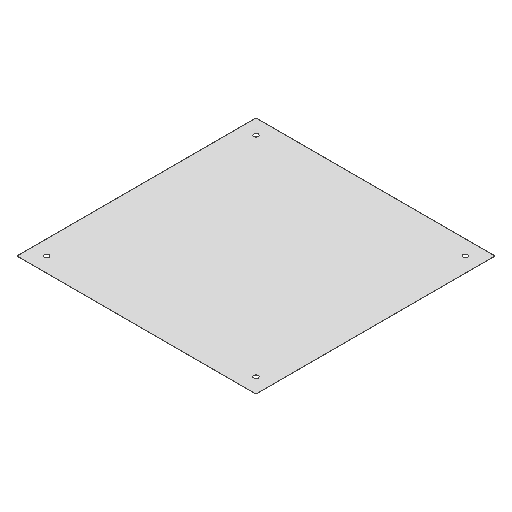
# Autodesk Inventor part: Film_B
Saved by Autodesk Inventor 2026 (Build 300175050, 175E)
## iProperties
Created: 2025-09-08
Part Number: Film_B
Material: Generic
Document SubType Name: Sheet Metal
Designer: kamig
Density: 1 g/cm^3
Sheet Metal Rule: Default
Appearance: Default
Author: kamig
Autodesk Inventor part; units mm, degrees
ref_plane "YZ Plane" through (0, 0, 0) normal (1, 0, 0) x (0, 1, 0)
ref_plane "XZ Plane" through (0, 0, 0) normal (0, 1, 0) x (-1, 0, 0)
ref_plane "XY Plane" through (0, 0, 0) normal (0, 0, 1) x (1, 0, 0)
sketch "スケッチ1" plane through (0, 0, 0) normal (0, 1, 0) x (-1, 0, 0)
  line L0 (80, 80) -> (-80, 80)
  line L1 (-80, 80) -> (-80, -80)
  line L2 (-80, -80) -> (80, -80)
  line L3 (80, -80) -> (80, 80)
  line L4 (80, 80) -> (-80, -80) construction
  line L5 (-80, 80) -> (80, -80) construction
  point P0 (0, 0)
  dimension "d0" = 160
  dimension "d1" = 160
  constraints: 12 end point, 2 midpoint, 2 parallel, 1 horizontal, 1 perpendicular
  measures "d0" distance of L0.end L1.end
  measures "d1" distance of L1.end L2.end
extrude "押し出し1" add sketch "スケッチ1" against normal blind 0.1
sketch "スケッチ2" plane through (0, 0, 0) normal (0, 1, 0) x (1, 0, 0)
  circle A0 centre (-70, 70) radius 1.55
  line L0 (-80, 80) -> (-80, -80) projected
  line L1 (80, 80) -> (-80, 80) projected
  circle A1 centre (70, 70) radius 1.55
  circle A2 centre (70, -70) radius 1.55
  circle A3 centre (-70, -70) radius 1.55
  line L2 (-80, -80) -> (80, -80) projected
  line L3 (80, -80) -> (80, 80) projected
  point P0 (0, 0)
  dimension "d4" = 3.1
  dimension "d5" = 10
  dimension "d6" = 10
  dimension "d7" = 10
  dimension "d8" = 10
  dimension "d9" = 3.1
  dimension "d10" = 10
  dimension "d11" = 10
  dimension "d12" = 3.1
  dimension "d13" = 10
  dimension "d14" = 10
  dimension "d15" = 3.1
  constraints: 4 centre point
  measures "d4" diameter of A0
  measures "d5" distance from line of A0.centre L0
  measures "d6" distance from line of A0.centre L1
  measures "d7" distance from line of L0 A3.centre
  measures "d8" distance from line of L2 A3.centre
  measures "d9" diameter of A3
  measures "d10" distance from line of L2 A2.centre
  measures "d11" distance from line of L3 A2.centre
  measures "d12" diameter of A2
  measures "d13" distance from line of L3 A1.centre
  measures "d14" distance from line of A1.centre L1
  measures "d15" diameter of A1
extrude "押し出し2" cut sketch "スケッチ2" against normal blind 0.1 contours A0 | A1 | A2 | A3
equation "\"BendRadius\" = Thickness"
equation "\"BendReliefWidth\" = Thickness"
equation "\"BendReliefDepth\" = 0.5 * Thickness"
equation "\"CornerReliefSize\" = 4 * Thickness"
equation "\"MinimumRemnant\" = 2 * Thickness"
equation "\"TransitionRadius\" = BendRadius"
equation "\"JacobiRadiusSize\" = BendRadius"
equation "\"GapSize\" = Thickness"
equation "\"Thickness\" = 3.048"
